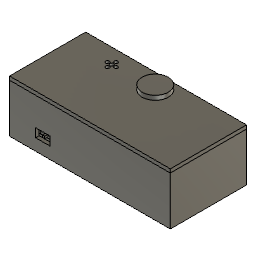
final (Autodesk Fusion 360 design; units mm, degrees)
part number: 2026-10-25-23-15-52-196
Autodesk Fusion 360 part; units mm, degrees
sketch "Boceto1" plane through (0, 0, 0) normal (0, 0, 1) x (1, 0, 0)
  line L0 (0, 0) -> (111, 0)
  line L1 (111, 0) -> (111, 52.6)
  line L2 (111, 52.6) -> (0, 52.6)
  line L3 (0, 52.6) -> (0, 0)
extrude "Extruir1" add sketch "Boceto1" along normal blind 33.5 makes body 1
ref_plane "PlanoDeObra1" through (0, 0, 2.5) normal (0, 0, 1) x (1, 0, 0)
sketch "Boceto2" plane through (0, 0, 2.5) normal (0, 0, 1) x (1, 0, 0)
  line L0 (2.5, 2.5) -> (108.5, 2.5)
  line L1 (108.5, 2.5) -> (108.5, 50.1)
  line L2 (108.5, 50.1) -> (2.5, 50.1)
  line L3 (2.5, 50.1) -> (2.5, 2.5)
extrude "Extruir2" cut sketch "Boceto2" along normal blind 32 bodies 1
ref_plane "PlanoDeObra2" through (0, 0, 2) normal (0, 0, 1) x (1, 0, 0)
sketch "Boceto3" plane through (0, 0, 2) normal (0, 0, 1) x (1, 0, 0)
  line L0 (2.5, 32.5) -> (108.5, 32.5)
  line L1 (108.5, 32.5) -> (108.5, 34.1)
  line L2 (108.5, 34.1) -> (2.5, 34.1)
  line L3 (2.5, 34.1) -> (2.5, 32.5)
extrude "Extruir3" add sketch "Boceto3" along normal blind 20.5 bodies 1
ref_plane "PlanoDeObra3" through (0, 0, 10.5) normal (0, 0, 1) x (1, 0, 0)
sketch "Boceto4" plane through (0, 0, 10.5) normal (0, 0, 1) x (1, 0, 0)
  line L0 (49.5, 32) -> (61.5, 32)
  line L1 (61.5, 32) -> (61.5, 34.6)
  line L2 (61.5, 34.6) -> (49.5, 34.6)
  line L3 (49.5, 34.6) -> (49.5, 32)
extrude "Extruir4" cut sketch "Boceto4" along normal blind 13 bodies 1
sketch "Boceto5" plane through (0, 0, 2) normal (0, 0, 1) x (1, 0, 0)
  line L0 (3, 3) -> (7, 3)
  line L1 (7, 3) -> (7, 7)
  line L2 (7, 7) -> (3, 7)
  line L3 (3, 7) -> (3, 3)
extrude "Extruir5" add sketch "Boceto5" along normal blind 5.5 bodies 1
sketch "Boceto6" plane through (0, 0, 2) normal (0, 0, 1) x (1, 0, 0)
  line L0 (3, 28) -> (7, 28)
  line L1 (7, 28) -> (7, 32)
  line L2 (7, 32) -> (3, 32)
  line L3 (3, 32) -> (3, 28)
extrude "Extruir6" add sketch "Boceto6" along normal blind 5.5 bodies 1
sketch "Boceto7" plane through (0, 0, 2) normal (0, 0, 1) x (1, 0, 0)
  line L0 (104, 3) -> (108, 3)
  line L1 (108, 3) -> (108, 7)
  line L2 (108, 7) -> (104, 7)
  line L3 (104, 7) -> (104, 3)
extrude "Extruir7" add sketch "Boceto7" along normal blind 5.5 bodies 1
sketch "Boceto8" plane through (0, 0, 2) normal (0, 0, 1) x (1, 0, 0)
  line L0 (104, 28) -> (108, 28)
  line L1 (108, 28) -> (108, 32)
  line L2 (108, 32) -> (104, 32)
  line L3 (104, 32) -> (104, 28)
extrude "Extruir8" add sketch "Boceto8" along normal blind 5.5 bodies 1
sketch "Boceto9" plane through (0, 0, 2) normal (0, 0, 1) x (1, 0, 0)
  line L0 (3, 34.4) -> (37.5, 34.4)
  line L1 (37.5, 34.4) -> (37.5, 35.9)
  line L2 (37.5, 35.9) -> (3, 35.9)
  line L3 (3, 35.9) -> (3, 34.4)
extrude "Extruir9" add sketch "Boceto9" along normal blind 8.5 bodies 1
sketch "Boceto10" plane through (0, 0, 2) normal (0, 0, 1) x (1, 0, 0)
  line L0 (3, 48.3) -> (37.5, 48.3)
  line L1 (37.5, 48.3) -> (37.5, 49.8)
  line L2 (37.5, 49.8) -> (3, 49.8)
  line L3 (3, 49.8) -> (3, 48.3)
extrude "Extruir10" add sketch "Boceto10" along normal blind 8.5 bodies 1
ref_plane "PlanoDeObra4" through (0, 0, 8.1) normal (0, 0, 1) x (1, 0, 0)
sketch "Boceto11" plane through (0, 0, 8.1) normal (0, 0, 1) x (1, 0, 0)
  line L0 (18, -1) -> (28, -1)
  line L1 (28, -1) -> (28, 3)
  line L2 (28, 3) -> (18, 3)
  line L3 (18, 3) -> (18, -1)
extrude "Extruir11" cut sketch "Boceto11" along normal blind 6 bodies 1
ref_plane "PlanoDeObra5" through (0, 0, 33.5) normal (0, 0, 1) x (1, 0, 0)
sketch "Boceto12" plane through (0, 0, 33.5) normal (0, 0, 1) x (1, 0, 0)
  line L0 (0, 0) -> (111, 0)
  line L1 (111, 0) -> (111, 52.6)
  line L2 (111, 52.6) -> (0, 52.6)
  line L3 (0, 52.6) -> (0, 0)
extrude "Extruir12" add sketch "Boceto12" along normal blind 2.5 separate body makes body 2
ref_plane "PlanoDeObra6" through (0, 0, 30.5) normal (0, 0, 1) x (1, 0, 0)
sketch "Boceto13" plane through (0, 0, 30.5) normal (0, 0, 1) x (1, 0, 0)
  line L0 (2.65, 2.65) -> (108.35, 2.65)
  line L1 (108.35, 2.65) -> (108.35, 49.95)
  line L2 (108.35, 49.95) -> (2.65, 49.95)
  line L3 (2.65, 49.95) -> (2.65, 2.65)
extrude "Extruir13" add sketch "Boceto13" along normal blind 3.5 bodies 2
ref_plane "PlanoDeObra7" through (0, 0, 29.5) normal (0, 0, 1) x (1, 0, 0)
sketch "Boceto14" plane through (0, 0, 29.5) normal (0, 0, 1) x (1, 0, 0)
  line L0 (4.15, 4.15) -> (106.85, 4.15)
  line L1 (106.85, 4.15) -> (106.85, 48.45)
  line L2 (106.85, 48.45) -> (4.15, 48.45)
  line L3 (4.15, 48.45) -> (4.15, 4.15)
extrude "Extruir14" cut sketch "Boceto14" along normal blind 4 bodies 2
sketch "Boceto15" plane through (0, 0, 30.5) normal (0, 0, 1) x (1, 0, 0)
  line L0 (51.3, 34.9) -> (65.7, 34.9)
  line L1 (65.7, 34.9) -> (65.7, 49.3)
  line L2 (65.7, 49.3) -> (51.3, 49.3)
  line L3 (51.3, 49.3) -> (51.3, 34.9)
extrude "Extruir15" add sketch "Boceto15" along normal blind 3.5 bodies 2
sketch "Boceto16" plane through (0, 0, 29.5) normal (0, 0, 1) x (1, 0, 0)
  line L0 (52.3, 35.9) -> (64.7, 35.9)
  line L1 (64.7, 35.9) -> (64.7, 48.3)
  line L2 (64.7, 48.3) -> (52.3, 48.3)
  line L3 (52.3, 48.3) -> (52.3, 35.9)
extrude "Extruir16" cut sketch "Boceto16" along normal blind 4 bodies 2
sketch "Boceto17" plane through (0, 0, 30.5) normal (0, 0, 1) x (1, 0, 0)
  circle A0 centre (28.5, 42.1) radius 7
extrude "Extruir17" add sketch "Boceto17" along normal blind 3.5 bodies 2
sketch "Boceto18" plane through (0, 0, 29.5) normal (0, 0, 1) x (1, 0, 0)
  circle A0 centre (28.5, 42.1) radius 5.2
extrude "Extruir18" cut sketch "Boceto18" along normal blind 4 bodies 2
ref_plane "PlanoDeObra8" through (0, 0, 32.5) normal (0, 0, 1) x (1, 0, 0)
sketch "Boceto19" plane through (0, 0, 32.5) normal (0, 0, 1) x (1, 0, 0)
  circle A0 centre (58.5, 42.1) radius 5.95
extrude "Extruir19" cut sketch "Boceto19" along normal blind 4.5 bodies 2
sketch "Boceto20" plane through (0, 0, 32.5) normal (0, 0, 1) x (1, 0, 0)
  circle A0 centre (28.5, 42.1) radius 1.25
extrude "Extruir20" cut sketch "Boceto20" along normal blind 4.5 bodies 2
sketch "Boceto21" plane through (0, 0, 32.5) normal (0, 0, 1) x (1, 0, 0)
  circle A0 centre (25.5, 42.1) radius 1.25
extrude "Extruir21" cut sketch "Boceto21" along normal blind 4.5 bodies 2
sketch "Boceto22" plane through (0, 0, 32.5) normal (0, 0, 1) x (1, 0, 0)
  circle A0 centre (31.5, 42.1) radius 1.25
extrude "Extruir22" cut sketch "Boceto22" along normal blind 4.5 bodies 2
sketch "Boceto23" plane through (0, 0, 32.5) normal (0, 0, 1) x (1, 0, 0)
  circle A0 centre (28.5, 45.1) radius 1.25
extrude "Extruir23" cut sketch "Boceto23" along normal blind 4.5 bodies 2
sketch "Boceto24" plane through (0, 0, 32.5) normal (0, 0, 1) x (1, 0, 0)
  circle A0 centre (28.5, 39.1) radius 1.25
extrude "Extruir24" cut sketch "Boceto24" along normal blind 4.5 bodies 2
ref_plane "PlanoDeObra9" through (0, 0, 36) normal (0, 0, 1) x (1, 0, 0)
sketch "Boceto25" plane through (0, 0, 36) normal (0, 0, 1) x (1, 0, 0)
  circle A0 centre (58.5, 42.1) radius 9
extrude "Extruir25" add sketch "Boceto25" along normal blind 3 separate body makes body 3
sketch "Boceto26" plane through (0, 0, 32.5) normal (0, 0, 1) x (1, 0, 0)
  circle A0 centre (58.5, 42.1) radius 5.75
extrude "Extruir26" add sketch "Boceto26" along normal blind 4 bodies 3
ref_plane "PlanoDeObra10" through (0, 0, 7.5) normal (0, 0, 1) x (1, 0, 0)
sketch "Boceto27" plane through (0, 0, 7.5) normal (0, 0, 1) x (1, 0, 0)
  line L0 (3, 3) -> (108, 3)
  line L1 (108, 3) -> (108, 32)
  line L2 (108, 32) -> (3, 32)
  line L3 (3, 32) -> (3, 3)
extrude "Extruir27" add sketch "Boceto27" along normal blind 1.6 separate body makes body 4
ref_plane "PlanoDeObra11" through (0, 0, 9.1) normal (0, 0, 1) x (1, 0, 0)
sketch "Boceto28" plane through (0, 0, 9.1) normal (0, 0, 1) x (1, 0, 0)
  line L0 (17, 7) -> (94, 7)
  line L1 (94, 7) -> (94, 28)
  line L2 (94, 28) -> (17, 28)
  line L3 (17, 28) -> (17, 7)
extrude "Extruir28" add sketch "Boceto28" along normal blind 2 separate body makes body 5
sketch "Boceto29" plane through (0, 0, 9.1) normal (0, 0, 1) x (1, 0, 0)
  line L0 (17, 7) -> (20, 7)
  line L1 (20, 7) -> (20, 28)
  line L2 (20, 28) -> (17, 28)
  line L3 (17, 28) -> (17, 7)
extrude "Extruir29" add sketch "Boceto29" along normal blind 14 bodies 5
sketch "Boceto30" plane through (0, 0, 9.1) normal (0, 0, 1) x (1, 0, 0)
  line L0 (91, 7) -> (94, 7)
  line L1 (94, 7) -> (94, 28)
  line L2 (94, 28) -> (91, 28)
  line L3 (91, 28) -> (91, 7)
extrude "Extruir30" add sketch "Boceto30" along normal blind 14 bodies 5
ref_plane "PlanoDeObra12" through (55.5, 0, 0) normal (1, 0, 0) x (0, 1, 0)
sketch "Boceto31" plane through (55.5, 0, 0) normal (1, 0, 0) x (0, 0, -1)
  circle A0 centre (-20.3, 17.5) radius 9.2
extrude "Extruir31" add sketch "Boceto31" along normal mid plane 65 separate body makes body 6
ref_plane "PlanoDeObra13" through (88.5, 0, 0) normal (1, 0, 0) x (0, 1, 0)
sketch "Boceto32" plane through (88.5, 0, 0) normal (1, 0, 0) x (0, 0, -1)
  circle A0 centre (-20.3, 17.5) radius 2.5
extrude "Extruir32" add sketch "Boceto32" along normal mid plane 2 bodies 6
sketch "Boceto33" plane through (0, 0, 9.1) normal (0, 0, 1) x (1, 0, 0)
  line L0 (2.5, 13.75) -> (8.5, 13.75)
  line L1 (8.5, 13.75) -> (8.5, 21.25)
  line L2 (8.5, 21.25) -> (2.5, 21.25)
  line L3 (2.5, 21.25) -> (2.5, 13.75)
extrude "Extruir33" add sketch "Boceto33" along normal blind 2.6 separate body makes body 7
sketch "Boceto34" plane through (0, 0, 9.1) normal (0, 0, 1) x (1, 0, 0)
  line L0 (95, 10.9) -> (108, 10.9)
  line L1 (108, 10.9) -> (108, 24.1)
  line L2 (108, 24.1) -> (95, 24.1)
  line L3 (95, 24.1) -> (95, 10.9)
extrude "Extruir34" add sketch "Boceto34" along normal blind 5.7 separate body makes body 8
sketch "Boceto35" plane through (0, 0, 9.1) normal (0, 0, 1) x (1, 0, 0)
  line L0 (18.7, 3) -> (27.3, 3)
  line L1 (27.3, 3) -> (27.3, 6.6)
  line L2 (27.3, 6.6) -> (18.7, 6.6)
  line L3 (18.7, 6.6) -> (18.7, 3)
extrude "Extruir35" add sketch "Boceto35" along normal blind 3.5 separate body makes body 9
ref_plane "PlanoDeObra14" through (0, 0, 10.1) normal (0, 0, 1) x (1, 0, 0)
sketch "Boceto36" plane through (0, 0, 10.1) normal (0, 0, 1) x (1, 0, 0)
  line L0 (22.25, 0.5) -> (23.75, 0.5)
  line L1 (23.75, 0.5) -> (23.75, 3.5)
  line L2 (23.75, 3.5) -> (22.25, 3.5)
  line L3 (22.25, 3.5) -> (22.25, 0.5)
extrude "Extruir36" add sketch "Boceto36" along normal blind 1.5 bodies 9
sketch "Boceto37" plane through (0, 0, 9.1) normal (0, 0, 1) x (1, 0, 0)
  line L0 (88, 4.5) -> (89.6, 4.5)
  line L1 (89.6, 4.5) -> (89.6, 5.3)
  line L2 (89.6, 5.3) -> (88, 5.3)
  line L3 (88, 5.3) -> (88, 4.5)
extrude "Extruir37" add sketch "Boceto37" along normal blind 0.6 separate body makes body 10
sketch "Boceto38" plane through (0, 0, 9.1) normal (0, 0, 1) x (1, 0, 0)
  line L0 (91, 4.5) -> (92.6, 4.5)
  line L1 (92.6, 4.5) -> (92.6, 5.3)
  line L2 (92.6, 5.3) -> (91, 5.3)
  line L3 (91, 5.3) -> (91, 4.5)
extrude "Extruir38" add sketch "Boceto38" along normal blind 0.6 separate body makes body 11
sketch "Boceto39" plane through (0, 0, 2.5) normal (0, 0, 1) x (1, 0, 0)
  line L0 (3, 38.9) -> (37.5, 38.9)
  line L1 (37.5, 38.9) -> (37.5, 40.5)
  line L2 (37.5, 40.5) -> (3, 40.5)
  line L3 (3, 40.5) -> (3, 38.9)
extrude "Extruir39" add sketch "Boceto39" along normal blind 26 separate body makes body 12
sketch "Boceto40" plane through (0, 0, 7.5) normal (0, 0, 1) x (1, 0, 0)
  line L0 (13.5, 40.5) -> (37.5, 40.5)
  line L1 (37.5, 40.5) -> (37.5, 43.7)
  line L2 (37.5, 43.7) -> (13.5, 43.7)
  line L3 (13.5, 43.7) -> (13.5, 40.5)
extrude "Extruir40" add sketch "Boceto40" along normal blind 16 separate body makes body 13
ref_plane "PlanoDeObra15" through (0, 0, 11.75) normal (0, 0, 1) x (1, 0, 0)
sketch "Boceto41" plane through (0, 0, 11.75) normal (0, 0, 1) x (1, 0, 0)
  line L0 (2.5, 40.5) -> (8.5, 40.5)
  line L1 (8.5, 40.5) -> (8.5, 43.1)
  line L2 (8.5, 43.1) -> (2.5, 43.1)
  line L3 (2.5, 43.1) -> (2.5, 40.5)
extrude "Extruir41" add sketch "Boceto41" along normal blind 7.5 separate body makes body 14
ref_plane "PlanoDeObra16" through (0, 0, 21.5) normal (0, 0, 1) x (1, 0, 0)
sketch "Boceto42" plane through (0, 0, 21.5) normal (0, 0, 1) x (1, 0, 0)
  line L0 (4, 40.5) -> (7.5, 40.5)
  line L1 (7.5, 40.5) -> (7.5, 42.5)
  line L2 (7.5, 42.5) -> (4, 42.5)
  line L3 (4, 42.5) -> (4, 40.5)
extrude "Extruir42" add sketch "Boceto42" along normal blind 4 separate body makes body 15
sketch "Boceto43" plane through (0, 0, 10.5) normal (0, 0, 1) x (1, 0, 0)
  line L0 (15, 37.4) -> (25, 37.4)
  line L1 (25, 37.4) -> (25, 38.9)
  line L2 (25, 38.9) -> (15, 38.9)
  line L3 (15, 38.9) -> (15, 37.4)
extrude "Extruir43" add sketch "Boceto43" along normal blind 5 separate body makes body 16
ref_plane "PlanoDeObra17" through (0, 0, 2.53) normal (0, 0, 1) x (1, 0, 0)
sketch "Boceto44" plane through (0, 0, 2.53) normal (0, 0, 1) x (1, 0, 0)
  line L0 (10.09, 40.5) -> (30.41, 40.5)
  line L1 (30.41, 40.5) -> (30.41, 43)
  line L2 (30.41, 43) -> (10.09, 43)
  line L3 (10.09, 43) -> (10.09, 40.5)
extrude "Extruir44" add sketch "Boceto44" along normal blind 2.54 separate body makes body 17
ref_plane "PlanoDeObra18" through (0, 0, 3.48) normal (0, 0, 1) x (1, 0, 0)
sketch "Boceto45" plane through (0, 0, 3.48) normal (0, 0, 1) x (1, 0, 0)
  line L0 (11.04, 35.9) -> (11.68, 35.9)
  line L1 (11.68, 35.9) -> (11.68, 48.3)
  line L2 (11.68, 48.3) -> (11.04, 48.3)
  line L3 (11.04, 48.3) -> (11.04, 35.9)
extrude "Extruir45" add sketch "Boceto45" along normal blind 0.64 bodies 17
sketch "Boceto46" plane through (0, 0, 3.48) normal (0, 0, 1) x (1, 0, 0)
  line L0 (13.58, 35.9) -> (14.22, 35.9)
  line L1 (14.22, 35.9) -> (14.22, 48.3)
  line L2 (14.22, 48.3) -> (13.58, 48.3)
  line L3 (13.58, 48.3) -> (13.58, 35.9)
extrude "Extruir46" add sketch "Boceto46" along normal blind 0.64 bodies 17
sketch "Boceto47" plane through (0, 0, 3.48) normal (0, 0, 1) x (1, 0, 0)
  line L0 (16.12, 35.9) -> (16.76, 35.9)
  line L1 (16.76, 35.9) -> (16.76, 48.3)
  line L2 (16.76, 48.3) -> (16.12, 48.3)
  line L3 (16.12, 48.3) -> (16.12, 35.9)
extrude "Extruir47" add sketch "Boceto47" along normal blind 0.64 bodies 17
sketch "Boceto48" plane through (0, 0, 3.48) normal (0, 0, 1) x (1, 0, 0)
  line L0 (18.66, 35.9) -> (19.3, 35.9)
  line L1 (19.3, 35.9) -> (19.3, 48.3)
  line L2 (19.3, 48.3) -> (18.66, 48.3)
  line L3 (18.66, 48.3) -> (18.66, 35.9)
extrude "Extruir48" add sketch "Boceto48" along normal blind 0.64 bodies 17
sketch "Boceto49" plane through (0, 0, 3.48) normal (0, 0, 1) x (1, 0, 0)
  line L0 (21.2, 35.9) -> (21.84, 35.9)
  line L1 (21.84, 35.9) -> (21.84, 48.3)
  line L2 (21.84, 48.3) -> (21.2, 48.3)
  line L3 (21.2, 48.3) -> (21.2, 35.9)
extrude "Extruir49" add sketch "Boceto49" along normal blind 0.64 bodies 17
sketch "Boceto50" plane through (0, 0, 3.48) normal (0, 0, 1) x (1, 0, 0)
  line L0 (23.74, 35.9) -> (24.38, 35.9)
  line L1 (24.38, 35.9) -> (24.38, 48.3)
  line L2 (24.38, 48.3) -> (23.74, 48.3)
  line L3 (23.74, 48.3) -> (23.74, 35.9)
extrude "Extruir50" add sketch "Boceto50" along normal blind 0.64 bodies 17
sketch "Boceto51" plane through (0, 0, 3.48) normal (0, 0, 1) x (1, 0, 0)
  line L0 (26.28, 35.9) -> (26.92, 35.9)
  line L1 (26.92, 35.9) -> (26.92, 48.3)
  line L2 (26.92, 48.3) -> (26.28, 48.3)
  line L3 (26.28, 48.3) -> (26.28, 35.9)
extrude "Extruir51" add sketch "Boceto51" along normal blind 0.64 bodies 17
sketch "Boceto52" plane through (0, 0, 3.48) normal (0, 0, 1) x (1, 0, 0)
  line L0 (28.82, 35.9) -> (29.46, 35.9)
  line L1 (29.46, 35.9) -> (29.46, 48.3)
  line L2 (29.46, 48.3) -> (28.82, 48.3)
  line L3 (28.82, 48.3) -> (28.82, 35.9)
extrude "Extruir52" add sketch "Boceto52" along normal blind 0.64 bodies 17
ref_plane "PlanoDeObra19" through (0, 0, 25.93) normal (0, 0, 1) x (1, 0, 0)
sketch "Boceto53" plane through (0, 0, 25.93) normal (0, 0, 1) x (1, 0, 0)
  line L0 (10.09, 40.5) -> (30.41, 40.5)
  line L1 (30.41, 40.5) -> (30.41, 43)
  line L2 (30.41, 43) -> (10.09, 43)
  line L3 (10.09, 43) -> (10.09, 40.5)
extrude "Extruir53" add sketch "Boceto53" along normal blind 2.54 separate body makes body 18
ref_plane "PlanoDeObra20" through (0, 0, 26.88) normal (0, 0, 1) x (1, 0, 0)
sketch "Boceto54" plane through (0, 0, 26.88) normal (0, 0, 1) x (1, 0, 0)
  line L0 (11.04, 35.9) -> (11.68, 35.9)
  line L1 (11.68, 35.9) -> (11.68, 48.3)
  line L2 (11.68, 48.3) -> (11.04, 48.3)
  line L3 (11.04, 48.3) -> (11.04, 35.9)
extrude "Extruir54" add sketch "Boceto54" along normal blind 0.64 bodies 18
sketch "Boceto55" plane through (0, 0, 26.88) normal (0, 0, 1) x (1, 0, 0)
  line L0 (13.58, 35.9) -> (14.22, 35.9)
  line L1 (14.22, 35.9) -> (14.22, 48.3)
  line L2 (14.22, 48.3) -> (13.58, 48.3)
  line L3 (13.58, 48.3) -> (13.58, 35.9)
extrude "Extruir55" add sketch "Boceto55" along normal blind 0.64 bodies 18
sketch "Boceto56" plane through (0, 0, 26.88) normal (0, 0, 1) x (1, 0, 0)
  line L0 (16.12, 35.9) -> (16.76, 35.9)
  line L1 (16.76, 35.9) -> (16.76, 48.3)
  line L2 (16.76, 48.3) -> (16.12, 48.3)
  line L3 (16.12, 48.3) -> (16.12, 35.9)
extrude "Extruir56" add sketch "Boceto56" along normal blind 0.64 bodies 18
sketch "Boceto57" plane through (0, 0, 26.88) normal (0, 0, 1) x (1, 0, 0)
  line L0 (18.66, 35.9) -> (19.3, 35.9)
  line L1 (19.3, 35.9) -> (19.3, 48.3)
  line L2 (19.3, 48.3) -> (18.66, 48.3)
  line L3 (18.66, 48.3) -> (18.66, 35.9)
extrude "Extruir57" add sketch "Boceto57" along normal blind 0.64 bodies 18
sketch "Boceto58" plane through (0, 0, 26.88) normal (0, 0, 1) x (1, 0, 0)
  line L0 (21.2, 35.9) -> (21.84, 35.9)
  line L1 (21.84, 35.9) -> (21.84, 48.3)
  line L2 (21.84, 48.3) -> (21.2, 48.3)
  line L3 (21.2, 48.3) -> (21.2, 35.9)
extrude "Extruir58" add sketch "Boceto58" along normal blind 0.64 bodies 18
sketch "Boceto59" plane through (0, 0, 26.88) normal (0, 0, 1) x (1, 0, 0)
  line L0 (23.74, 35.9) -> (24.38, 35.9)
  line L1 (24.38, 35.9) -> (24.38, 48.3)
  line L2 (24.38, 48.3) -> (23.74, 48.3)
  line L3 (23.74, 48.3) -> (23.74, 35.9)
extrude "Extruir59" add sketch "Boceto59" along normal blind 0.64 bodies 18
sketch "Boceto60" plane through (0, 0, 26.88) normal (0, 0, 1) x (1, 0, 0)
  line L0 (26.28, 35.9) -> (26.92, 35.9)
  line L1 (26.92, 35.9) -> (26.92, 48.3)
  line L2 (26.92, 48.3) -> (26.28, 48.3)
  line L3 (26.28, 48.3) -> (26.28, 35.9)
extrude "Extruir60" add sketch "Boceto60" along normal blind 0.64 bodies 18
sketch "Boceto61" plane through (0, 0, 26.88) normal (0, 0, 1) x (1, 0, 0)
  line L0 (28.82, 35.9) -> (29.46, 35.9)
  line L1 (29.46, 35.9) -> (29.46, 48.3)
  line L2 (29.46, 48.3) -> (28.82, 48.3)
  line L3 (28.82, 48.3) -> (28.82, 35.9)
extrude "Extruir61" add sketch "Boceto61" along normal blind 0.64 bodies 18
ref_plane "PlanoDeObra21" through (0, 0, 11.5) normal (0, 0, 1) x (1, 0, 0)
sketch "Boceto62" plane through (0, 0, 11.5) normal (0, 0, 1) x (1, 0, 0)
  line L0 (52.75, 28.5) -> (54.25, 28.5)
  line L1 (54.25, 28.5) -> (54.25, 38.1)
  line L2 (54.25, 38.1) -> (52.75, 38.1)
  line L3 (52.75, 38.1) -> (52.75, 28.5)
extrude "Extruir62" add sketch "Boceto62" along normal blind 1.5 separate body makes body 19
sketch "Boceto63" plane through (0, 0, 11.5) normal (0, 0, 1) x (1, 0, 0)
  line L0 (54.75, 28.5) -> (56.25, 28.5)
  line L1 (56.25, 28.5) -> (56.25, 38.1)
  line L2 (56.25, 38.1) -> (54.75, 38.1)
  line L3 (54.75, 38.1) -> (54.75, 28.5)
extrude "Extruir63" add sketch "Boceto63" along normal blind 1.5 separate body makes body 20
sketch "Boceto64" plane through (0, 0, 11.5) normal (0, 0, 1) x (1, 0, 0)
  line L0 (56.75, 28.5) -> (58.25, 28.5)
  line L1 (58.25, 28.5) -> (58.25, 38.1)
  line L2 (58.25, 38.1) -> (56.75, 38.1)
  line L3 (56.75, 38.1) -> (56.75, 28.5)
extrude "Extruir64" add sketch "Boceto64" along normal blind 1.5 separate body makes body 21
ref_plane "PlanoDeObra22" through (0, 0, 28) normal (0, 0, 1) x (1, 0, 0)
sketch "Boceto65" plane through (0, 0, 28) normal (0, 0, 1) x (1, 0, 0)
  circle A0 centre (28.5, 42.1) radius 5
extrude "Extruir65" add sketch "Boceto65" along normal blind 5.5 separate body makes body 22
ref_plane "PlanoDeObra23" through (0, 0, 24) normal (0, 0, 1) x (1, 0, 0)
sketch "Boceto66" plane through (0, 0, 24) normal (0, 0, 1) x (1, 0, 0)
  circle A0 centre (31, 42.1) radius 0.3
extrude "Extruir66" add sketch "Boceto66" along normal blind 4.5 bodies 22
sketch "Boceto67" plane through (0, 0, 24) normal (0, 0, 1) x (1, 0, 0)
  circle A0 centre (26, 42.1) radius 0.3
extrude "Extruir67" add sketch "Boceto67" along normal blind 4.5 bodies 22
ref_plane "PlanoDeObra24" through (0, 0, 28.9) normal (0, 0, 1) x (1, 0, 0)
sketch "Boceto68" plane through (0, 0, 28.9) normal (0, 0, 1) x (1, 0, 0)
  line L0 (52.5, 36.1) -> (64.5, 36.1)
  line L1 (64.5, 36.1) -> (64.5, 48.1)
  line L2 (64.5, 48.1) -> (52.5, 48.1)
  line L3 (52.5, 48.1) -> (52.5, 36.1)
extrude "Extruir68" add sketch "Boceto68" along normal blind 3.6 separate body makes body 23
ref_plane "PlanoDeObra25" through (0, 0, 25.4) normal (0, 0, 1) x (1, 0, 0)
sketch "Boceto69" plane through (0, 0, 25.4) normal (0, 0, 1) x (1, 0, 0)
  line L0 (64.35, 39.4) -> (65.15, 39.4)
  line L1 (65.15, 39.4) -> (65.15, 39.8)
  line L2 (65.15, 39.8) -> (64.35, 39.8)
  line L3 (64.35, 39.8) -> (64.35, 39.4)
extrude "Extruir69" add sketch "Boceto69" along normal blind 4 bodies 23
sketch "Boceto70" plane through (0, 0, 25.4) normal (0, 0, 1) x (1, 0, 0)
  line L0 (64.35, 44.4) -> (65.15, 44.4)
  line L1 (65.15, 44.4) -> (65.15, 44.8)
  line L2 (65.15, 44.8) -> (64.35, 44.8)
  line L3 (64.35, 44.8) -> (64.35, 44.4)
extrude "Extruir70" add sketch "Boceto70" along normal blind 4 bodies 23
sketch "Boceto71" plane through (0, 0, 25.4) normal (0, 0, 1) x (1, 0, 0)
  line L0 (51.85, 39.4) -> (52.65, 39.4)
  line L1 (52.65, 39.4) -> (52.65, 39.8)
  line L2 (52.65, 39.8) -> (51.85, 39.8)
  line L3 (51.85, 39.8) -> (51.85, 39.4)
extrude "Extruir71" add sketch "Boceto71" along normal blind 4 bodies 23
sketch "Boceto72" plane through (0, 0, 25.4) normal (0, 0, 1) x (1, 0, 0)
  line L0 (51.85, 44.4) -> (52.65, 44.4)
  line L1 (52.65, 44.4) -> (52.65, 44.8)
  line L2 (52.65, 44.8) -> (51.85, 44.8)
  line L3 (51.85, 44.8) -> (51.85, 44.4)
extrude "Extruir72" add sketch "Boceto72" along normal blind 4 bodies 23
named bodies: "Base", "Tapa", "Pulsador", "UPS_placa", "UPS_portapilas", "UPS_pila_18650", "UPS_microUSB_carga", "UPS_USB_A_salida", "UPS_interruptor", "UPS_LED_1", "UPS_LED_2", "Wemos_placa", "Wemos_ESP12", "Wemos_microUSB", "Wemos_reset", "Wemos_CH340", "Wemos_pines_1", "Wemos_pines_2", "Cable_1", "Cable_2", "Cable_3", "Buzzer", "Microswitch"
